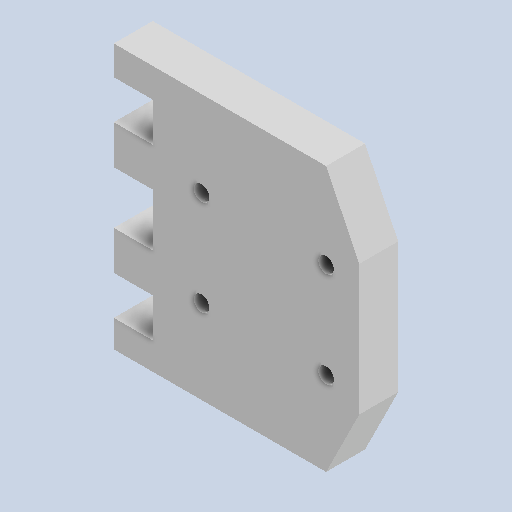
# Autodesk Inventor part: NeckFront
Saved by Autodesk Inventor 2025.2 (Build 292293000, 293)
## iProperties
Created: 2025-06-29
Part Number: NeckFront
Material: Generic
Document SubType Name: Modeling
Designer: ricoa
Density: 1 g/cm^3
Appearance: Default
Author: ricoa
Autodesk Inventor part; units mm, degrees
ref_plane "YZ Plane" through (0, 0, 0) normal (1, 0, 0) x (0, 1, 0)
ref_plane "XZ Plane" through (0, 0, 0) normal (0, 1, 0) x (-1, 0, 0)
ref_plane "XY Plane" through (0, 0, 0) normal (0, 0, 1) x (1, 0, 0)
sketch "Sketch1" plane through (0, 0, 0) normal (0, 0, 1) x (1, 0, 0)
  line L0 (-2, -17) -> (-2, -0.25) projected
  circle A0 centre (-6.25, -2.5) radius 1 projected
  circle A1 centre (-22.25, -2.5) radius 1 projected
  line L1 (-26.5, -17) -> (-28.5, -17) projected
  line L2 (-26.5, -0.25) -> (-28.5, -0.25) projected
  line L3 (-28.5, -17) -> (-33.5, -17)
  line L4 (-33.5, -17) -> (-33.5, -12)
  line L5 (-33.5, -12) -> (-28.5, -12)
  line L6 (-28.5, -0.25) -> (-33.5, -0.25)
  line L7 (-33.5, -0.25) -> (-33.5, -5.25)
  line L8 (-33.5, -5.25) -> (-28.5, -5.25)
  line L9 (-28.5, -5.25) -> (-28.5, -12)
  line L10 (-26.3964, 8.5) -> (-2.1036, 8.5) projected
  line L11 (-2.1036, -25.5) -> (-10.25, -25.5) projected
  line L12 (-2, -0.25) -> (-6.25, 8.5)
  line L13 (-33.5, 4.75) -> (-33.5, 8.5) projected
  line L14 (-28.5, 4.75) -> (-33.5, 4.75) projected
  line L15 (-28.5, -0.25) -> (-28.5, 4.75) projected
  line L16 (-28.5, -22) -> (-28.5, -17) projected
  line L17 (-28.5, -22) -> (-33.5, -22) projected
  line L18 (-33.5, -25.5) -> (-33.5, -22) projected
  line L19 (-6.25, 8.5) -> (-33.5, 8.5)
  line L20 (-33.5, -25.5) -> (-6.25, -25.5)
  line L21 (-2, -17) -> (-6.25, -25.5)
  line L22 (-6.25, -2.5) -> (-6.25, 8.5)
  line L23 (-6.25, -25.5) -> (-6.25, -2.5) construction
  point P0 (0, 0)
  dimension "d0" = 5
  dimension "d1" = 5
  dimension "d2" = 5
  constraints: 26 end point, 6 perpendicular, 4 point on line, 3 horizontal, 1 collinear
  measures "d0" distance of L1.end L3.end
  measures "d1" distance of L3.end L4.end
  measures "d2" distance of L6.end L7.end
extrude "Extrusion1" add sketch "Sketch1" along normal blind 5
sketch "Sketch2" plane through (0, 0, 5) normal (0, 0, 1) x (1, 0, 0)
  line L0 (-28.5, -5.25) -> (-28.5, -12) projected
  line L1 (-28.5, -8.625) -> (-23.8125, -8.625)
  circle A0 centre (-22.25, -2.5) radius 1 projected
  circle A1 centre (-6.25, -2.5) radius 1 projected
  circle A2 centre (-22.25, -14.75) radius 1
  circle A3 centre (-6.25, -14.75) radius 1
  point P0 (0, 0)
  constraints: 2 centre point, 2 end point, 2 symmetric about line, 1 horizontal, 1 midpoint, 2 other
extrude "Extrusion2" cut sketch "Sketch2" against normal blind 5 contours A2 | A3
body "Solid1"
